Autodesk Fusion 360 part; units mm, degrees
(part 8 of 8)
equation "d2441 = ( ( ( keyRowTwo ) - holderStemY ) - 5.1 mm ) + faceOriginV"
equation "d2442 = ( ( ( ( layoutGap + keycapSize / 2 + 1 * keyPitch ) - holderStemX ) - holderFrameX / 2 - 0.1 mm ) + ( holderFrameX / 2 - holderWidth / 2 + 0.1 mm ) ) - ( ( ( layoutGap + keycapSize / 2 + 1 * keyPitch ) - holderStemX ) - holderFrameX / 2 - 0.1 mm )"
equation "d2443 = ( ( ( ( ( keyRowTwo ) - holderStemY ) - 5.1 mm ) + faceOriginV ) + ( 7.8 mm ) ) - ( ( ( ( keyRowTwo ) - holderStemY ) - 5.1 mm ) + faceOriginV )"
equation "d2444 = -( holderHeight + holderHookThickness - 1.2 mm + 0.2 mm )"
equation "d2446 = ( ( layoutGap + keycapSize / 2 + 1 * keyPitch ) - holderStemX ) + holderWidth / 2"
equation "d2447 = ( ( ( keyRowTwo ) - holderStemY ) - 5.1 mm ) + faceOriginV"
equation "d2448 = ( ( ( ( layoutGap + keycapSize / 2 + 1 * keyPitch ) - holderStemX ) + holderWidth / 2 ) + ( holderFrameX / 2 - holderWidth / 2 + 0.1 mm ) ) - ( ( ( layoutGap + keycapSize / 2 + 1 * keyPitch ) - holderStemX ) + holderWidth / 2 )"
equation "d2449 = ( ( ( ( ( keyRowTwo ) - holderStemY ) - 5.1 mm ) + faceOriginV ) + ( 7.8 mm ) ) - ( ( ( ( keyRowTwo ) - holderStemY ) - 5.1 mm ) + faceOriginV )"
equation "d2450 = -( holderHeight + holderHookThickness - 1.2 mm + 0.2 mm )"
equation "d2452 = ( ( layoutGap + keycapSize / 2 + 1 * keyPitch ) - holderStemX ) + ( -2.5 mm ) - 1.2 mm"
equation "d2453 = ( ( ( ( keyRowTwo ) - holderStemY ) - 1.2 mm ) * cos(caseTilt) + ( holderBottomDepth + holderLidGap ) * sin(caseTilt) ) - 2.5 mm"
equation "d2454 = ( ( ( ( layoutGap + keycapSize / 2 + 1 * keyPitch ) - holderStemX ) + ( -2.5 mm ) - 1.2 mm ) + ( 2.4 mm ) ) - ( ( ( layoutGap + keycapSize / 2 + 1 * keyPitch ) - holderStemX ) + ( -2.5 mm ) - 1.2 mm )"
equation "d2455 = ( ( ( ( ( ( keyRowTwo ) - holderStemY ) - 1.2 mm ) * cos(caseTilt) + ( holderBottomDepth + holderLidGap ) * sin(caseTilt) ) - 2.5 mm ) + ( 5 mm ) ) - ( ( ( ( ( keyRowTwo ) - holderStemY ) - 1.2 mm ) * cos(caseTilt) + ( holderBottomDepth + holderLidGap ) * sin(caseTilt) ) - 2.5 mm )"
equation "d2456 = ( frontHeight + ( ( ( keyRowTwo ) - holderStemY ) - 1.2 mm ) * sin(caseTilt) - ( holderBottomDepth + holderLidGap ) * cos(caseTilt) ) - bottomThickness - 2 mm"
equation "d2458 = ( ( layoutGap + keycapSize / 2 + 1 * keyPitch ) - holderStemX ) + ( -2.5 mm ) - 0.5 mm"
equation "d2459 = ( ( ( ( keyRowTwo ) - holderStemY ) - 1.2 mm ) * cos(caseTilt) + ( holderBottomDepth + holderLidGap ) * sin(caseTilt) ) - 1.5 mm"
equation "d2460 = ( ( ( ( layoutGap + keycapSize / 2 + 1 * keyPitch ) - holderStemX ) + ( -2.5 mm ) - 0.5 mm ) + ( 1 mm ) ) - ( ( ( layoutGap + keycapSize / 2 + 1 * keyPitch ) - holderStemX ) + ( -2.5 mm ) - 0.5 mm )"
equation "d2461 = ( ( ( ( ( ( keyRowTwo ) - holderStemY ) - 1.2 mm ) * cos(caseTilt) + ( holderBottomDepth + holderLidGap ) * sin(caseTilt) ) - 1.5 mm ) + ( 3 mm ) ) - ( ( ( ( ( keyRowTwo ) - holderStemY ) - 1.2 mm ) * cos(caseTilt) + ( holderBottomDepth + holderLidGap ) * sin(caseTilt) ) - 1.5 mm )"
equation "d2462 = ( frontHeight + ( ( ( keyRowTwo ) - holderStemY ) - 1.2 mm ) * sin(caseTilt) - ( holderBottomDepth + holderLidGap ) * cos(caseTilt) ) - bottomThickness + 0.5 mm"
equation "d2464 = ( ( ( layoutGap + keycapSize / 2 + 1 * keyPitch ) - holderStemX ) + ( -2.5 mm ) - 0.5 mm ) - 0.1 mm"
equation "d2465 = ( ( ( ( keyRowTwo ) - holderStemY ) - 1.2 mm ) - 2 mm ) + faceOriginV"
equation "d2466 = ( ( ( ( ( layoutGap + keycapSize / 2 + 1 * keyPitch ) - holderStemX ) + ( -2.5 mm ) - 0.5 mm ) - 0.1 mm ) + ( 1.2 mm ) ) - ( ( ( ( layoutGap + keycapSize / 2 + 1 * keyPitch ) - holderStemX ) + ( -2.5 mm ) - 0.5 mm ) - 0.1 mm )"
equation "d2467 = ( ( ( ( ( ( keyRowTwo ) - holderStemY ) - 1.2 mm ) - 2 mm ) + faceOriginV ) + ( 4 mm ) ) - ( ( ( ( ( keyRowTwo ) - holderStemY ) - 1.2 mm ) - 2 mm ) + faceOriginV )"
equation "d2468 = rearHeight"
equation "d2470 = ( ( layoutGap + keycapSize / 2 + 1 * keyPitch ) - holderStemX ) + ( 2.5 mm ) - 1.2 mm"
equation "d2471 = ( ( ( ( keyRowTwo ) - holderStemY ) - 1.2 mm ) * cos(caseTilt) + ( holderBottomDepth + holderLidGap ) * sin(caseTilt) ) - 2.5 mm"
equation "d2472 = ( ( ( ( layoutGap + keycapSize / 2 + 1 * keyPitch ) - holderStemX ) + ( 2.5 mm ) - 1.2 mm ) + ( 2.4 mm ) ) - ( ( ( layoutGap + keycapSize / 2 + 1 * keyPitch ) - holderStemX ) + ( 2.5 mm ) - 1.2 mm )"
equation "d2473 = ( ( ( ( ( ( keyRowTwo ) - holderStemY ) - 1.2 mm ) * cos(caseTilt) + ( holderBottomDepth + holderLidGap ) * sin(caseTilt) ) - 2.5 mm ) + ( 5 mm ) ) - ( ( ( ( ( keyRowTwo ) - holderStemY ) - 1.2 mm ) * cos(caseTilt) + ( holderBottomDepth + holderLidGap ) * sin(caseTilt) ) - 2.5 mm )"
equation "d2474 = ( frontHeight + ( ( ( keyRowTwo ) - holderStemY ) - 1.2 mm ) * sin(caseTilt) - ( holderBottomDepth + holderLidGap ) * cos(caseTilt) ) - bottomThickness - 2 mm"
equation "d2476 = ( ( layoutGap + keycapSize / 2 + 1 * keyPitch ) - holderStemX ) + ( 2.5 mm ) - 0.5 mm"
equation "d2477 = ( ( ( ( keyRowTwo ) - holderStemY ) - 1.2 mm ) * cos(caseTilt) + ( holderBottomDepth + holderLidGap ) * sin(caseTilt) ) - 1.5 mm"
equation "d2478 = ( ( ( ( layoutGap + keycapSize / 2 + 1 * keyPitch ) - holderStemX ) + ( 2.5 mm ) - 0.5 mm ) + ( 1 mm ) ) - ( ( ( layoutGap + keycapSize / 2 + 1 * keyPitch ) - holderStemX ) + ( 2.5 mm ) - 0.5 mm )"
equation "d2479 = ( ( ( ( ( ( keyRowTwo ) - holderStemY ) - 1.2 mm ) * cos(caseTilt) + ( holderBottomDepth + holderLidGap ) * sin(caseTilt) ) - 1.5 mm ) + ( 3 mm ) ) - ( ( ( ( ( keyRowTwo ) - holderStemY ) - 1.2 mm ) * cos(caseTilt) + ( holderBottomDepth + holderLidGap ) * sin(caseTilt) ) - 1.5 mm )"
equation "d2480 = ( frontHeight + ( ( ( keyRowTwo ) - holderStemY ) - 1.2 mm ) * sin(caseTilt) - ( holderBottomDepth + holderLidGap ) * cos(caseTilt) ) - bottomThickness + 0.5 mm"
equation "d2482 = ( ( ( layoutGap + keycapSize / 2 + 1 * keyPitch ) - holderStemX ) + ( 2.5 mm ) - 0.5 mm ) - 0.1 mm"
equation "d2483 = ( ( ( ( keyRowTwo ) - holderStemY ) - 1.2 mm ) - 2 mm ) + faceOriginV"
equation "d2484 = ( ( ( ( ( layoutGap + keycapSize / 2 + 1 * keyPitch ) - holderStemX ) + ( 2.5 mm ) - 0.5 mm ) - 0.1 mm ) + ( 1.2 mm ) ) - ( ( ( ( layoutGap + keycapSize / 2 + 1 * keyPitch ) - holderStemX ) + ( 2.5 mm ) - 0.5 mm ) - 0.1 mm )"
equation "d2485 = ( ( ( ( ( ( keyRowTwo ) - holderStemY ) - 1.2 mm ) - 2 mm ) + faceOriginV ) + ( 4 mm ) ) - ( ( ( ( ( keyRowTwo ) - holderStemY ) - 1.2 mm ) - 2 mm ) + faceOriginV )"
equation "d2486 = rearHeight"
equation "d2488 = ( layoutGap + keycapSize / 2 + 2 * keyPitch ) - holderFrameX / 2"
equation "d2489 = ( ( keyRowTwo ) - holderFrameY / 2 ) + faceOriginV"
equation "d2490 = ( ( ( layoutGap + keycapSize / 2 + 2 * keyPitch ) - holderFrameX / 2 ) + ( holderFrameX ) ) - ( ( layoutGap + keycapSize / 2 + 2 * keyPitch ) - holderFrameX / 2 )"
equation "d2491 = ( ( ( ( keyRowTwo ) - holderFrameY / 2 ) + faceOriginV ) + ( holderFrameY ) ) - ( ( ( keyRowTwo ) - holderFrameY / 2 ) + faceOriginV )"
equation "d2492 = -( holderBottomDepth + holderHookThickness - shellWall - carrierClearance - carrierThickness )"
equation "d2494 = ( layoutGap + keycapSize / 2 + 2 * keyPitch ) - holderSwitchVoid / 2"
equation "d2495 = ( ( keyRowTwo ) - holderSwitchVoid / 2 ) + faceOriginV"
equation "d2496 = ( ( ( layoutGap + keycapSize / 2 + 2 * keyPitch ) - holderSwitchVoid / 2 ) + ( holderSwitchVoid ) ) - ( ( layoutGap + keycapSize / 2 + 2 * keyPitch ) - holderSwitchVoid / 2 )"
equation "d2497 = ( ( ( ( keyRowTwo ) - holderSwitchVoid / 2 ) + faceOriginV ) + ( holderSwitchVoid ) ) - ( ( ( keyRowTwo ) - holderSwitchVoid / 2 ) + faceOriginV )"
equation "d2498 = -( holderTopDepth - shellWall - carrierClearance - carrierThickness )"
equation "d2500 = ( ( layoutGap + keycapSize / 2 + 2 * keyPitch ) - holderStemX ) - holderWidth / 2 - holderFit"
equation "d2501 = ( ( ( keyRowTwo ) - holderStemY ) - holderLength / 2 - holderFit ) + faceOriginV"
equation "d2502 = ( ( ( ( layoutGap + keycapSize / 2 + 2 * keyPitch ) - holderStemX ) - holderWidth / 2 - holderFit ) + ( holderWidth + 2 * holderFit ) ) - ( ( ( layoutGap + keycapSize / 2 + 2 * keyPitch ) - holderStemX ) - holderWidth / 2 - holderFit )"
equation "d2503 = ( ( ( ( ( keyRowTwo ) - holderStemY ) - holderLength / 2 - holderFit ) + faceOriginV ) + ( holderLength + 2 * holderFit ) ) - ( ( ( ( keyRowTwo ) - holderStemY ) - holderLength / 2 - holderFit ) + faceOriginV )"
equation "d2504 = -( holderHeight + holderHookThickness + 0.2 mm )"
equation "d2506 = ( ( layoutGap + keycapSize / 2 + 2 * keyPitch ) - holderStemX ) - holderFrameX / 2 - 0.1 mm"
equation "d2507 = ( ( ( ( keyRowTwo ) - holderStemY ) + holderSpringY ) - holderSpringWidth / 2 - 0.6 mm ) + faceOriginV"
equation "d2508 = ( ( ( ( layoutGap + keycapSize / 2 + 2 * keyPitch ) - holderStemX ) - holderFrameX / 2 - 0.1 mm ) + ( holderFrameX / 2 - holderWidth / 2 - holderFit + 0.1 mm ) ) - ( ( ( layoutGap + keycapSize / 2 + 2 * keyPitch ) - holderStemX ) - holderFrameX / 2 - 0.1 mm )"
equation "d2509 = ( ( ( ( ( ( keyRowTwo ) - holderStemY ) + holderSpringY ) - holderSpringWidth / 2 - 0.6 mm ) + faceOriginV ) + ( 0.6 mm ) ) - ( ( ( ( ( keyRowTwo ) - holderStemY ) + holderSpringY ) - holderSpringWidth / 2 - 0.6 mm ) + faceOriginV )"
equation "d2510 = -( holderBottomDepth + holderHookThickness - shellWall - carrierClearance - carrierThickness - 1 mm + 0.2 mm )"
equation "d2512 = ( ( layoutGap + keycapSize / 2 + 2 * keyPitch ) - holderStemX ) - holderFrameX / 2 - 0.1 mm"
equation "d2513 = ( ( ( ( keyRowTwo ) - holderStemY ) + holderSpringY ) + holderSpringWidth / 2 ) + faceOriginV"
equation "d2514 = ( ( ( ( layoutGap + keycapSize / 2 + 2 * keyPitch ) - holderStemX ) - holderFrameX / 2 - 0.1 mm ) + ( holderFrameX / 2 - holderWidth / 2 - holderFit + 0.1 mm ) ) - ( ( ( layoutGap + keycapSize / 2 + 2 * keyPitch ) - holderStemX ) - holderFrameX / 2 - 0.1 mm )"
equation "d2515 = ( ( ( ( ( ( keyRowTwo ) - holderStemY ) + holderSpringY ) + holderSpringWidth / 2 ) + faceOriginV ) + ( 0.6 mm ) ) - ( ( ( ( ( keyRowTwo ) - holderStemY ) + holderSpringY ) + holderSpringWidth / 2 ) + faceOriginV )"
equation "d2516 = -( holderBottomDepth + holderHookThickness - shellWall - carrierClearance - carrierThickness - 1 mm + 0.2 mm )"
equation "d2518 = ( ( layoutGap + keycapSize / 2 + 2 * keyPitch ) - holderStemX ) - holderFrameX / 2 + 0.8 mm"
equation "d2519 = ( ( ( ( keyRowTwo ) - holderStemY ) + holderSpringY ) - holderSpringWidth / 2 ) + faceOriginV"
equation "d2520 = ( ( ( ( layoutGap + keycapSize / 2 + 2 * keyPitch ) - holderStemX ) - holderFrameX / 2 + 0.8 mm ) + ( holderFrameX / 2 - 0.8 mm - holderWidth / 2 - holderFit ) ) - ( ( ( layoutGap + keycapSize / 2 + 2 * keyPitch ) - holderStemX ) - holderFrameX / 2 + 0.8 mm )"
equation "d2521 = ( ( ( ( ( ( keyRowTwo ) - holderStemY ) + holderSpringY ) - holderSpringWidth / 2 ) + faceOriginV ) + ( holderSpringWidth ) ) - ( ( ( ( ( keyRowTwo ) - holderStemY ) + holderSpringY ) - holderSpringWidth / 2 ) + faceOriginV )"
equation "d2522 = -( holderHeight + holderHookThickness + 0.2 mm )"
equation "d2524 = ( ( layoutGap + keycapSize / 2 + 2 * keyPitch ) - holderStemX ) - holderFrameX / 2"
equation "d2525 = ( ( ( ( keyRowTwo ) - holderStemY ) + holderSpringY ) - holderSpringWidth / 2 ) + faceOriginV"
equation "d2526 = ( ( ( ( layoutGap + keycapSize / 2 + 2 * keyPitch ) - holderStemX ) - holderFrameX / 2 ) + ( holderFrameX / 2 - holderWidth / 2 + holderHookOverlap ) ) - ( ( ( layoutGap + keycapSize / 2 + 2 * keyPitch ) - holderStemX ) - holderFrameX / 2 )"
equation "d2527 = ( ( ( ( ( ( keyRowTwo ) - holderStemY ) + holderSpringY ) - holderSpringWidth / 2 ) + faceOriginV ) + ( holderSpringWidth ) ) - ( ( ( ( ( keyRowTwo ) - holderStemY ) + holderSpringY ) - holderSpringWidth / 2 ) + faceOriginV )"
equation "d2528 = -( holderHookThickness )"
equation "d2531 = ( ( layoutGap + keycapSize / 2 + 2 * keyPitch ) - holderStemX ) + holderWidth / 2 + holderFit"
equation "d2532 = ( ( ( ( keyRowTwo ) - holderStemY ) + holderSpringY ) - holderSpringWidth / 2 - 0.6 mm ) + faceOriginV"
equation "d2533 = ( ( ( ( layoutGap + keycapSize / 2 + 2 * keyPitch ) - holderStemX ) + holderWidth / 2 + holderFit ) + ( holderFrameX / 2 - holderWidth / 2 - holderFit + 0.1 mm ) ) - ( ( ( layoutGap + keycapSize / 2 + 2 * keyPitch ) - holderStemX ) + holderWidth / 2 + holderFit )"
equation "d2534 = ( ( ( ( ( ( keyRowTwo ) - holderStemY ) + holderSpringY ) - holderSpringWidth / 2 - 0.6 mm ) + faceOriginV ) + ( 0.6 mm ) ) - ( ( ( ( ( keyRowTwo ) - holderStemY ) + holderSpringY ) - holderSpringWidth / 2 - 0.6 mm ) + faceOriginV )"
equation "d2535 = -( holderBottomDepth + holderHookThickness - shellWall - carrierClearance - carrierThickness - 1 mm + 0.2 mm )"
equation "d2537 = ( ( layoutGap + keycapSize / 2 + 2 * keyPitch ) - holderStemX ) + holderWidth / 2 + holderFit"
equation "d2538 = ( ( ( ( keyRowTwo ) - holderStemY ) + holderSpringY ) + holderSpringWidth / 2 ) + faceOriginV"
equation "d2539 = ( ( ( ( layoutGap + keycapSize / 2 + 2 * keyPitch ) - holderStemX ) + holderWidth / 2 + holderFit ) + ( holderFrameX / 2 - holderWidth / 2 - holderFit + 0.1 mm ) ) - ( ( ( layoutGap + keycapSize / 2 + 2 * keyPitch ) - holderStemX ) + holderWidth / 2 + holderFit )"
equation "d2540 = ( ( ( ( ( ( keyRowTwo ) - holderStemY ) + holderSpringY ) + holderSpringWidth / 2 ) + faceOriginV ) + ( 0.6 mm ) ) - ( ( ( ( ( keyRowTwo ) - holderStemY ) + holderSpringY ) + holderSpringWidth / 2 ) + faceOriginV )"
equation "d2541 = -( holderBottomDepth + holderHookThickness - shellWall - carrierClearance - carrierThickness - 1 mm + 0.2 mm )"
equation "d2543 = ( ( layoutGap + keycapSize / 2 + 2 * keyPitch ) - holderStemX ) + holderWidth / 2 + holderFit"
equation "d2544 = ( ( ( ( keyRowTwo ) - holderStemY ) + holderSpringY ) - holderSpringWidth / 2 ) + faceOriginV"
equation "d2545 = ( ( ( ( layoutGap + keycapSize / 2 + 2 * keyPitch ) - holderStemX ) + holderWidth / 2 + holderFit ) + ( holderFrameX / 2 - 0.8 mm - holderWidth / 2 - holderFit ) ) - ( ( ( layoutGap + keycapSize / 2 + 2 * keyPitch ) - holderStemX ) + holderWidth / 2 + holderFit )"
equation "d2546 = ( ( ( ( ( ( keyRowTwo ) - holderStemY ) + holderSpringY ) - holderSpringWidth / 2 ) + faceOriginV ) + ( holderSpringWidth ) ) - ( ( ( ( ( keyRowTwo ) - holderStemY ) + holderSpringY ) - holderSpringWidth / 2 ) + faceOriginV )"
equation "d2547 = -( holderHeight + holderHookThickness + 0.2 mm )"
equation "d2549 = ( ( layoutGap + keycapSize / 2 + 2 * keyPitch ) - holderStemX ) + holderWidth / 2 - holderHookOverlap"
equation "d2550 = ( ( ( ( keyRowTwo ) - holderStemY ) + holderSpringY ) - holderSpringWidth / 2 ) + faceOriginV"
equation "d2551 = ( ( ( ( layoutGap + keycapSize / 2 + 2 * keyPitch ) - holderStemX ) + holderWidth / 2 - holderHookOverlap ) + ( holderFrameX / 2 - holderWidth / 2 + holderHookOverlap ) ) - ( ( ( layoutGap + keycapSize / 2 + 2 * keyPitch ) - holderStemX ) + holderWidth / 2 - holderHookOverlap )"
equation "d2552 = ( ( ( ( ( ( keyRowTwo ) - holderStemY ) + holderSpringY ) - holderSpringWidth / 2 ) + faceOriginV ) + ( holderSpringWidth ) ) - ( ( ( ( ( keyRowTwo ) - holderStemY ) + holderSpringY ) - holderSpringWidth / 2 ) + faceOriginV )"
equation "d2553 = -( holderHookThickness )"
equation "d2556 = ( ( layoutGap + keycapSize / 2 + 2 * keyPitch ) - holderStemX ) + ( -3 mm ) - 0.5 mm"
equation "d2557 = ( ( ( keyRowTwo ) - holderStemY ) + 4 mm ) + faceOriginV"
equation "d2558 = ( ( ( ( layoutGap + keycapSize / 2 + 2 * keyPitch ) - holderStemX ) + ( -3 mm ) - 0.5 mm ) + ( 1 mm ) ) - ( ( ( layoutGap + keycapSize / 2 + 2 * keyPitch ) - holderStemX ) + ( -3 mm ) - 0.5 mm )"
equation "d2559 = ( ( ( ( ( keyRowTwo ) - holderStemY ) + 4 mm ) + faceOriginV ) + ( holderFrameY / 2 - 4 mm ) ) - ( ( ( ( keyRowTwo ) - holderStemY ) + 4 mm ) + faceOriginV )"
equation "d2562 = ( ( layoutGap + keycapSize / 2 + 2 * keyPitch ) - holderStemX ) + ( 3 mm ) - 0.5 mm"
equation "d2563 = ( ( ( keyRowTwo ) - holderStemY ) + 4 mm ) + faceOriginV"
equation "d2564 = ( ( ( ( layoutGap + keycapSize / 2 + 2 * keyPitch ) - holderStemX ) + ( 3 mm ) - 0.5 mm ) + ( 1 mm ) ) - ( ( ( layoutGap + keycapSize / 2 + 2 * keyPitch ) - holderStemX ) + ( 3 mm ) - 0.5 mm )"
equation "d2565 = ( ( ( ( ( keyRowTwo ) - holderStemY ) + 4 mm ) + faceOriginV ) + ( holderFrameY / 2 - 4 mm ) ) - ( ( ( ( keyRowTwo ) - holderStemY ) + 4 mm ) + faceOriginV )"
equation "d2568 = ( ( layoutGap + keycapSize / 2 + 2 * keyPitch ) - holderStemX ) - holderFrameX / 2 - 0.1 mm"
equation "d2569 = ( ( ( keyRowTwo ) - holderStemY ) - 5.1 mm ) + faceOriginV"
equation "d2570 = ( ( ( ( layoutGap + keycapSize / 2 + 2 * keyPitch ) - holderStemX ) - holderFrameX / 2 - 0.1 mm ) + ( holderFrameX / 2 - holderWidth / 2 + 0.1 mm ) ) - ( ( ( layoutGap + keycapSize / 2 + 2 * keyPitch ) - holderStemX ) - holderFrameX / 2 - 0.1 mm )"
equation "d2571 = ( ( ( ( ( keyRowTwo ) - holderStemY ) - 5.1 mm ) + faceOriginV ) + ( 7.8 mm ) ) - ( ( ( ( keyRowTwo ) - holderStemY ) - 5.1 mm ) + faceOriginV )"
equation "d2572 = -( holderHeight + holderHookThickness - 1.2 mm + 0.2 mm )"
equation "d2574 = ( ( layoutGap + keycapSize / 2 + 2 * keyPitch ) - holderStemX ) + holderWidth / 2"
equation "d2575 = ( ( ( keyRowTwo ) - holderStemY ) - 5.1 mm ) + faceOriginV"
equation "d2576 = ( ( ( ( layoutGap + keycapSize / 2 + 2 * keyPitch ) - holderStemX ) + holderWidth / 2 ) + ( holderFrameX / 2 - holderWidth / 2 + 0.1 mm ) ) - ( ( ( layoutGap + keycapSize / 2 + 2 * keyPitch ) - holderStemX ) + holderWidth / 2 )"
equation "d2577 = ( ( ( ( ( keyRowTwo ) - holderStemY ) - 5.1 mm ) + faceOriginV ) + ( 7.8 mm ) ) - ( ( ( ( keyRowTwo ) - holderStemY ) - 5.1 mm ) + faceOriginV )"
equation "d2578 = -( holderHeight + holderHookThickness - 1.2 mm + 0.2 mm )"
equation "d2580 = ( ( layoutGap + keycapSize / 2 + 2 * keyPitch ) - holderStemX ) + ( -2.5 mm ) - 1.2 mm"
equation "d2581 = ( ( ( ( keyRowTwo ) - holderStemY ) - 1.2 mm ) * cos(caseTilt) + ( holderBottomDepth + holderLidGap ) * sin(caseTilt) ) - 2.5 mm"
equation "d2582 = ( ( ( ( layoutGap + keycapSize / 2 + 2 * keyPitch ) - holderStemX ) + ( -2.5 mm ) - 1.2 mm ) + ( 2.4 mm ) ) - ( ( ( layoutGap + keycapSize / 2 + 2 * keyPitch ) - holderStemX ) + ( -2.5 mm ) - 1.2 mm )"
equation "d2583 = ( ( ( ( ( ( keyRowTwo ) - holderStemY ) - 1.2 mm ) * cos(caseTilt) + ( holderBottomDepth + holderLidGap ) * sin(caseTilt) ) - 2.5 mm ) + ( 5 mm ) ) - ( ( ( ( ( keyRowTwo ) - holderStemY ) - 1.2 mm ) * cos(caseTilt) + ( holderBottomDepth + holderLidGap ) * sin(caseTilt) ) - 2.5 mm )"
equation "d2584 = ( frontHeight + ( ( ( keyRowTwo ) - holderStemY ) - 1.2 mm ) * sin(caseTilt) - ( holderBottomDepth + holderLidGap ) * cos(caseTilt) ) - bottomThickness - 2 mm"
equation "d2586 = ( ( layoutGap + keycapSize / 2 + 2 * keyPitch ) - holderStemX ) + ( -2.5 mm ) - 0.5 mm"
equation "d2587 = ( ( ( ( keyRowTwo ) - holderStemY ) - 1.2 mm ) * cos(caseTilt) + ( holderBottomDepth + holderLidGap ) * sin(caseTilt) ) - 1.5 mm"
equation "d2588 = ( ( ( ( layoutGap + keycapSize / 2 + 2 * keyPitch ) - holderStemX ) + ( -2.5 mm ) - 0.5 mm ) + ( 1 mm ) ) - ( ( ( layoutGap + keycapSize / 2 + 2 * keyPitch ) - holderStemX ) + ( -2.5 mm ) - 0.5 mm )"
equation "d2589 = ( ( ( ( ( ( keyRowTwo ) - holderStemY ) - 1.2 mm ) * cos(caseTilt) + ( holderBottomDepth + holderLidGap ) * sin(caseTilt) ) - 1.5 mm ) + ( 3 mm ) ) - ( ( ( ( ( keyRowTwo ) - holderStemY ) - 1.2 mm ) * cos(caseTilt) + ( holderBottomDepth + holderLidGap ) * sin(caseTilt) ) - 1.5 mm )"
equation "d2590 = ( frontHeight + ( ( ( keyRowTwo ) - holderStemY ) - 1.2 mm ) * sin(caseTilt) - ( holderBottomDepth + holderLidGap ) * cos(caseTilt) ) - bottomThickness + 0.5 mm"
equation "d2592 = ( ( ( layoutGap + keycapSize / 2 + 2 * keyPitch ) - holderStemX ) + ( -2.5 mm ) - 0.5 mm ) - 0.1 mm"
equation "d2593 = ( ( ( ( keyRowTwo ) - holderStemY ) - 1.2 mm ) - 2 mm ) + faceOriginV"
equation "d2594 = ( ( ( ( ( layoutGap + keycapSize / 2 + 2 * keyPitch ) - holderStemX ) + ( -2.5 mm ) - 0.5 mm ) - 0.1 mm ) + ( 1.2 mm ) ) - ( ( ( ( layoutGap + keycapSize / 2 + 2 * keyPitch ) - holderStemX ) + ( -2.5 mm ) - 0.5 mm ) - 0.1 mm )"
equation "d2595 = ( ( ( ( ( ( keyRowTwo ) - holderStemY ) - 1.2 mm ) - 2 mm ) + faceOriginV ) + ( 4 mm ) ) - ( ( ( ( ( keyRowTwo ) - holderStemY ) - 1.2 mm ) - 2 mm ) + faceOriginV )"
equation "d2596 = rearHeight"
equation "d2598 = ( ( layoutGap + keycapSize / 2 + 2 * keyPitch ) - holderStemX ) + ( 2.5 mm ) - 1.2 mm"
equation "d2599 = ( ( ( ( keyRowTwo ) - holderStemY ) - 1.2 mm ) * cos(caseTilt) + ( holderBottomDepth + holderLidGap ) * sin(caseTilt) ) - 2.5 mm"
equation "d2600 = ( ( ( ( layoutGap + keycapSize / 2 + 2 * keyPitch ) - holderStemX ) + ( 2.5 mm ) - 1.2 mm ) + ( 2.4 mm ) ) - ( ( ( layoutGap + keycapSize / 2 + 2 * keyPitch ) - holderStemX ) + ( 2.5 mm ) - 1.2 mm )"
equation "d2601 = ( ( ( ( ( ( keyRowTwo ) - holderStemY ) - 1.2 mm ) * cos(caseTilt) + ( holderBottomDepth + holderLidGap ) * sin(caseTilt) ) - 2.5 mm ) + ( 5 mm ) ) - ( ( ( ( ( keyRowTwo ) - holderStemY ) - 1.2 mm ) * cos(caseTilt) + ( holderBottomDepth + holderLidGap ) * sin(caseTilt) ) - 2.5 mm )"
equation "d2602 = ( frontHeight + ( ( ( keyRowTwo ) - holderStemY ) - 1.2 mm ) * sin(caseTilt) - ( holderBottomDepth + holderLidGap ) * cos(caseTilt) ) - bottomThickness - 2 mm"
equation "d2604 = ( ( layoutGap + keycapSize / 2 + 2 * keyPitch ) - holderStemX ) + ( 2.5 mm ) - 0.5 mm"
equation "d2605 = ( ( ( ( keyRowTwo ) - holderStemY ) - 1.2 mm ) * cos(caseTilt) + ( holderBottomDepth + holderLidGap ) * sin(caseTilt) ) - 1.5 mm"
equation "d2606 = ( ( ( ( layoutGap + keycapSize / 2 + 2 * keyPitch ) - holderStemX ) + ( 2.5 mm ) - 0.5 mm ) + ( 1 mm ) ) - ( ( ( layoutGap + keycapSize / 2 + 2 * keyPitch ) - holderStemX ) + ( 2.5 mm ) - 0.5 mm )"
equation "d2607 = ( ( ( ( ( ( keyRowTwo ) - holderStemY ) - 1.2 mm ) * cos(caseTilt) + ( holderBottomDepth + holderLidGap ) * sin(caseTilt) ) - 1.5 mm ) + ( 3 mm ) ) - ( ( ( ( ( keyRowTwo ) - holderStemY ) - 1.2 mm ) * cos(caseTilt) + ( holderBottomDepth + holderLidGap ) * sin(caseTilt) ) - 1.5 mm )"
equation "d2608 = ( frontHeight + ( ( ( keyRowTwo ) - holderStemY ) - 1.2 mm ) * sin(caseTilt) - ( holderBottomDepth + holderLidGap ) * cos(caseTilt) ) - bottomThickness + 0.5 mm"
equation "d2610 = ( ( ( layoutGap + keycapSize / 2 + 2 * keyPitch ) - holderStemX ) + ( 2.5 mm ) - 0.5 mm ) - 0.1 mm"
equation "d2611 = ( ( ( ( keyRowTwo ) - holderStemY ) - 1.2 mm ) - 2 mm ) + faceOriginV"
equation "d2612 = ( ( ( ( ( layoutGap + keycapSize / 2 + 2 * keyPitch ) - holderStemX ) + ( 2.5 mm ) - 0.5 mm ) - 0.1 mm ) + ( 1.2 mm ) ) - ( ( ( ( layoutGap + keycapSize / 2 + 2 * keyPitch ) - holderStemX ) + ( 2.5 mm ) - 0.5 mm ) - 0.1 mm )"
equation "d2613 = ( ( ( ( ( ( keyRowTwo ) - holderStemY ) - 1.2 mm ) - 2 mm ) + faceOriginV ) + ( 4 mm ) ) - ( ( ( ( ( keyRowTwo ) - holderStemY ) - 1.2 mm ) - 2 mm ) + faceOriginV )"
equation "d2614 = rearHeight"
equation "d2616 = layoutGap + ( displayWidth - oledBoardWidth ) / 2 - oledFitClearance"
equation "d2617 = ( controlCenter - oledBoardLength / 2 - oledFitClearance ) + faceOriginV"
equation "d2618 = ( ( layoutGap + ( displayWidth - oledBoardWidth ) / 2 - oledFitClearance ) + ( oledBoardWidth + 2 * oledFitClearance ) ) - ( layoutGap + ( displayWidth - oledBoardWidth ) / 2 - oledFitClearance )"
equation "d2619 = ( ( ( controlCenter - oledBoardLength / 2 - oledFitClearance ) + faceOriginV ) + ( oledBoardLength + 2 * oledFitClearance ) ) - ( ( controlCenter - oledBoardLength / 2 - oledFitClearance ) + faceOriginV )"
equation "d2620 = -( oledBackDepth + oledFitClearance - shellWall - carrierClearance )"
equation "d2622 = ( 115 mm ) - 11 mm"
equation "d2623 = ( ( keyRowOne ) - 11 mm ) + faceOriginV"
equation "d2624 = ( ( ( 115 mm ) - 11 mm ) + ( 22 mm ) ) - ( ( 115 mm ) - 11 mm )"
equation "d2625 = ( ( ( ( keyRowOne ) - 11 mm ) + faceOriginV ) + ( 22 mm ) ) - ( ( ( keyRowOne ) - 11 mm ) + faceOriginV )"
equation "d2626 = -( carrierThickness )"
equation "d2628 = ( 115 mm ) - switchOpening / 2"
equation "d2629 = ( ( keyRowOne ) - switchOpening / 2 ) + faceOriginV"
equation "d2630 = ( ( ( 115 mm ) - switchOpening / 2 ) + ( switchOpening ) ) - ( ( 115 mm ) - switchOpening / 2 )"
equation "d2631 = ( ( ( ( keyRowOne ) - switchOpening / 2 ) + faceOriginV ) + ( switchOpening ) ) - ( ( ( keyRowOne ) - switchOpening / 2 ) + faceOriginV )"
equation "d2632 = -( carrierThickness + 0.1 mm )"
equation "d2634 = ( 115 mm ) - holderFrameX / 2"
equation "d2635 = ( ( keyRowOne ) - holderFrameY / 2 ) + faceOriginV"
equation "d2636 = ( ( ( 115 mm ) - holderFrameX / 2 ) + ( holderFrameX ) ) - ( ( 115 mm ) - holderFrameX / 2 )"
equation "d2637 = ( ( ( ( keyRowOne ) - holderFrameY / 2 ) + faceOriginV ) + ( holderFrameY ) ) - ( ( ( keyRowOne ) - holderFrameY / 2 ) + faceOriginV )"
equation "d2638 = -( holderBottomDepth + holderHookThickness - shellWall - carrierClearance - carrierThickness )"
equation "d2640 = ( 115 mm ) - holderSwitchVoid / 2"
equation "d2641 = ( ( keyRowOne ) - holderSwitchVoid / 2 ) + faceOriginV"
equation "d2642 = ( ( ( 115 mm ) - holderSwitchVoid / 2 ) + ( holderSwitchVoid ) ) - ( ( 115 mm ) - holderSwitchVoid / 2 )"
equation "d2643 = ( ( ( ( keyRowOne ) - holderSwitchVoid / 2 ) + faceOriginV ) + ( holderSwitchVoid ) ) - ( ( ( keyRowOne ) - holderSwitchVoid / 2 ) + faceOriginV )"
equation "d2644 = -( holderTopDepth - shellWall - carrierClearance - carrierThickness )"
equation "d2646 = ( ( 115 mm ) - holderStemX ) - holderWidth / 2 - holderFit"
equation "d2647 = ( ( ( keyRowOne ) - holderStemY ) - holderLength / 2 - holderFit ) + faceOriginV"
equation "d2648 = ( ( ( ( 115 mm ) - holderStemX ) - holderWidth / 2 - holderFit ) + ( holderWidth + 2 * holderFit ) ) - ( ( ( 115 mm ) - holderStemX ) - holderWidth / 2 - holderFit )"
equation "d2649 = ( ( ( ( ( keyRowOne ) - holderStemY ) - holderLength / 2 - holderFit ) + faceOriginV ) + ( holderLength + 2 * holderFit ) ) - ( ( ( ( keyRowOne ) - holderStemY ) - holderLength / 2 - holderFit ) + faceOriginV )"
equation "d2650 = -( holderHeight + holderHookThickness + 0.2 mm )"
equation "d2652 = ( ( 115 mm ) - holderStemX ) - holderFrameX / 2 - 0.1 mm"
equation "d2653 = ( ( ( ( keyRowOne ) - holderStemY ) + holderSpringY ) - holderSpringWidth / 2 - 0.6 mm ) + faceOriginV"
equation "d2654 = ( ( ( ( 115 mm ) - holderStemX ) - holderFrameX / 2 - 0.1 mm ) + ( holderFrameX / 2 - holderWidth / 2 - holderFit + 0.1 mm ) ) - ( ( ( 115 mm ) - holderStemX ) - holderFrameX / 2 - 0.1 mm )"
equation "d2655 = ( ( ( ( ( ( keyRowOne ) - holderStemY ) + holderSpringY ) - holderSpringWidth / 2 - 0.6 mm ) + faceOriginV ) + ( 0.6 mm ) ) - ( ( ( ( ( keyRowOne ) - holderStemY ) + holderSpringY ) - holderSpringWidth / 2 - 0.6 mm ) + faceOriginV )"
equation "d2656 = -( holderBottomDepth + holderHookThickness - shellWall - carrierClearance - carrierThickness - 1 mm + 0.2 mm )"
equation "d2658 = ( ( 115 mm ) - holderStemX ) - holderFrameX / 2 - 0.1 mm"
equation "d2659 = ( ( ( ( keyRowOne ) - holderStemY ) + holderSpringY ) + holderSpringWidth / 2 ) + faceOriginV"
equation "d2660 = ( ( ( ( 115 mm ) - holderStemX ) - holderFrameX / 2 - 0.1 mm ) + ( holderFrameX / 2 - holderWidth / 2 - holderFit + 0.1 mm ) ) - ( ( ( 115 mm ) - holderStemX ) - holderFrameX / 2 - 0.1 mm )"
equation "d2661 = ( ( ( ( ( ( keyRowOne ) - holderStemY ) + holderSpringY ) + holderSpringWidth / 2 ) + faceOriginV ) + ( 0.6 mm ) ) - ( ( ( ( ( keyRowOne ) - holderStemY ) + holderSpringY ) + holderSpringWidth / 2 ) + faceOriginV )"
equation "d2662 = -( holderBottomDepth + holderHookThickness - shellWall - carrierClearance - carrierThickness - 1 mm + 0.2 mm )"
equation "d2664 = ( ( 115 mm ) - holderStemX ) - holderFrameX / 2 + 0.8 mm"
equation "d2665 = ( ( ( ( keyRowOne ) - holderStemY ) + holderSpringY ) - holderSpringWidth / 2 ) + faceOriginV"
equation "d2666 = ( ( ( ( 115 mm ) - holderStemX ) - holderFrameX / 2 + 0.8 mm ) + ( holderFrameX / 2 - 0.8 mm - holderWidth / 2 - holderFit ) ) - ( ( ( 115 mm ) - holderStemX ) - holderFrameX / 2 + 0.8 mm )"
equation "d2667 = ( ( ( ( ( ( keyRowOne ) - holderStemY ) + holderSpringY ) - holderSpringWidth / 2 ) + faceOriginV ) + ( holderSpringWidth ) ) - ( ( ( ( ( keyRowOne ) - holderStemY ) + holderSpringY ) - holderSpringWidth / 2 ) + faceOriginV )"
equation "d2668 = -( holderHeight + holderHookThickness + 0.2 mm )"
equation "d2670 = ( ( 115 mm ) - holderStemX ) - holderFrameX / 2"
equation "d2671 = ( ( ( ( keyRowOne ) - holderStemY ) + holderSpringY ) - holderSpringWidth / 2 ) + faceOriginV"
equation "d2672 = ( ( ( ( 115 mm ) - holderStemX ) - holderFrameX / 2 ) + ( holderFrameX / 2 - holderWidth / 2 + holderHookOverlap ) ) - ( ( ( 115 mm ) - holderStemX ) - holderFrameX / 2 )"
equation "d2673 = ( ( ( ( ( ( keyRowOne ) - holderStemY ) + holderSpringY ) - holderSpringWidth / 2 ) + faceOriginV ) + ( holderSpringWidth ) ) - ( ( ( ( ( keyRowOne ) - holderStemY ) + holderSpringY ) - holderSpringWidth / 2 ) + faceOriginV )"
equation "d2674 = -( holderHookThickness )"
equation "d2677 = ( ( 115 mm ) - holderStemX ) + holderWidth / 2 + holderFit"
equation "d2678 = ( ( ( ( keyRowOne ) - holderStemY ) + holderSpringY ) - holderSpringWidth / 2 - 0.6 mm ) + faceOriginV"
equation "d2679 = ( ( ( ( 115 mm ) - holderStemX ) + holderWidth / 2 + holderFit ) + ( holderFrameX / 2 - holderWidth / 2 - holderFit + 0.1 mm ) ) - ( ( ( 115 mm ) - holderStemX ) + holderWidth / 2 + holderFit )"
equation "d2680 = ( ( ( ( ( ( keyRowOne ) - holderStemY ) + holderSpringY ) - holderSpringWidth / 2 - 0.6 mm ) + faceOriginV ) + ( 0.6 mm ) ) - ( ( ( ( ( keyRowOne ) - holderStemY ) + holderSpringY ) - holderSpringWidth / 2 - 0.6 mm ) + faceOriginV )"
equation "d2681 = -( holderBottomDepth + holderHookThickness - shellWall - carrierClearance - carrierThickness - 1 mm + 0.2 mm )"
equation "d2683 = ( ( 115 mm ) - holderStemX ) + holderWidth / 2 + holderFit"
equation "d2684 = ( ( ( ( keyRowOne ) - holderStemY ) + holderSpringY ) + holderSpringWidth / 2 ) + faceOriginV"
equation "d2685 = ( ( ( ( 115 mm ) - holderStemX ) + holderWidth / 2 + holderFit ) + ( holderFrameX / 2 - holderWidth / 2 - holderFit + 0.1 mm ) ) - ( ( ( 115 mm ) - holderStemX ) + holderWidth / 2 + holderFit )"
equation "d2686 = ( ( ( ( ( ( keyRowOne ) - holderStemY ) + holderSpringY ) + holderSpringWidth / 2 ) + faceOriginV ) + ( 0.6 mm ) ) - ( ( ( ( ( keyRowOne ) - holderStemY ) + holderSpringY ) + holderSpringWidth / 2 ) + faceOriginV )"
equation "d2687 = -( holderBottomDepth + holderHookThickness - shellWall - carrierClearance - carrierThickness - 1 mm + 0.2 mm )"
equation "d2689 = ( ( 115 mm ) - holderStemX ) + holderWidth / 2 + holderFit"
equation "d2690 = ( ( ( ( keyRowOne ) - holderStemY ) + holderSpringY ) - holderSpringWidth / 2 ) + faceOriginV"
equation "d2691 = ( ( ( ( 115 mm ) - holderStemX ) + holderWidth / 2 + holderFit ) + ( holderFrameX / 2 - 0.8 mm - holderWidth / 2 - holderFit ) ) - ( ( ( 115 mm ) - holderStemX ) + holderWidth / 2 + holderFit )"
equation "d2692 = ( ( ( ( ( ( keyRowOne ) - holderStemY ) + holderSpringY ) - holderSpringWidth / 2 ) + faceOriginV ) + ( holderSpringWidth ) ) - ( ( ( ( ( keyRowOne ) - holderStemY ) + holderSpringY ) - holderSpringWidth / 2 ) + faceOriginV )"
equation "d2693 = -( holderHeight + holderHookThickness + 0.2 mm )"
equation "d2695 = ( ( 115 mm ) - holderStemX ) + holderWidth / 2 - holderHookOverlap"
equation "d2696 = ( ( ( ( keyRowOne ) - holderStemY ) + holderSpringY ) - holderSpringWidth / 2 ) + faceOriginV"
equation "d2697 = ( ( ( ( 115 mm ) - holderStemX ) + holderWidth / 2 - holderHookOverlap ) + ( holderFrameX / 2 - holderWidth / 2 + holderHookOverlap ) ) - ( ( ( 115 mm ) - holderStemX ) + holderWidth / 2 - holderHookOverlap )"
equation "d2698 = ( ( ( ( ( ( keyRowOne ) - holderStemY ) + holderSpringY ) - holderSpringWidth / 2 ) + faceOriginV ) + ( holderSpringWidth ) ) - ( ( ( ( ( keyRowOne ) - holderStemY ) + holderSpringY ) - holderSpringWidth / 2 ) + faceOriginV )"
equation "d2699 = -( holderHookThickness )"
equation "d2702 = ( ( 115 mm ) - holderStemX ) + ( -3 mm ) - 0.5 mm"
equation "d2703 = ( ( ( keyRowOne ) - holderStemY ) + 4 mm ) + faceOriginV"
equation "d2704 = ( ( ( ( 115 mm ) - holderStemX ) + ( -3 mm ) - 0.5 mm ) + ( 1 mm ) ) - ( ( ( 115 mm ) - holderStemX ) + ( -3 mm ) - 0.5 mm )"
equation "d2705 = ( ( ( ( ( keyRowOne ) - holderStemY ) + 4 mm ) + faceOriginV ) + ( holderFrameY / 2 - 4 mm ) ) - ( ( ( ( keyRowOne ) - holderStemY ) + 4 mm ) + faceOriginV )"
equation "d2708 = ( ( 115 mm ) - holderStemX ) + ( 3 mm ) - 0.5 mm"
equation "d2709 = ( ( ( keyRowOne ) - holderStemY ) + 4 mm ) + faceOriginV"
equation "d2710 = ( ( ( ( 115 mm ) - holderStemX ) + ( 3 mm ) - 0.5 mm ) + ( 1 mm ) ) - ( ( ( 115 mm ) - holderStemX ) + ( 3 mm ) - 0.5 mm )"
equation "d2711 = ( ( ( ( ( keyRowOne ) - holderStemY ) + 4 mm ) + faceOriginV ) + ( holderFrameY / 2 - 4 mm ) ) - ( ( ( ( keyRowOne ) - holderStemY ) + 4 mm ) + faceOriginV )"
equation "d2714 = ( ( 115 mm ) - holderStemX ) - holderFrameX / 2 - 0.1 mm"
equation "d2715 = ( ( ( keyRowOne ) - holderStemY ) - 5.1 mm ) + faceOriginV"
equation "d2716 = ( ( ( ( 115 mm ) - holderStemX ) - holderFrameX / 2 - 0.1 mm ) + ( holderFrameX / 2 - holderWidth / 2 + 0.1 mm ) ) - ( ( ( 115 mm ) - holderStemX ) - holderFrameX / 2 - 0.1 mm )"
equation "d2717 = ( ( ( ( ( keyRowOne ) - holderStemY ) - 5.1 mm ) + faceOriginV ) + ( 7.8 mm ) ) - ( ( ( ( keyRowOne ) - holderStemY ) - 5.1 mm ) + faceOriginV )"
equation "d2718 = -( holderHeight + holderHookThickness - 1.2 mm + 0.2 mm )"
equation "d2720 = ( ( 115 mm ) - holderStemX ) + holderWidth / 2"
equation "d2721 = ( ( ( keyRowOne ) - holderStemY ) - 5.1 mm ) + faceOriginV"
equation "d2722 = ( ( ( ( 115 mm ) - holderStemX ) + holderWidth / 2 ) + ( holderFrameX / 2 - holderWidth / 2 + 0.1 mm ) ) - ( ( ( 115 mm ) - holderStemX ) + holderWidth / 2 )"
equation "d2723 = ( ( ( ( ( keyRowOne ) - holderStemY ) - 5.1 mm ) + faceOriginV ) + ( 7.8 mm ) ) - ( ( ( ( keyRowOne ) - holderStemY ) - 5.1 mm ) + faceOriginV )"
equation "d2724 = -( holderHeight + holderHookThickness - 1.2 mm + 0.2 mm )"
equation "d2726 = ( 115 mm ) - 11 mm"
equation "d2727 = ( ( keyRowOne ) * cos(caseTilt) + ( holderBottomDepth + holderLidGap ) * sin(caseTilt) ) - 11 mm"
equation "d2728 = ( ( ( 115 mm ) - 11 mm ) + ( 22 mm ) ) - ( ( 115 mm ) - 11 mm )"
equation "d2729 = ( ( ( ( keyRowOne ) * cos(caseTilt) + ( holderBottomDepth + holderLidGap ) * sin(caseTilt) ) - 11 mm ) + ( 22 mm ) ) - ( ( ( keyRowOne ) * cos(caseTilt) + ( holderBottomDepth + holderLidGap ) * sin(caseTilt) ) - 11 mm )"
equation "d2730 = bottomThickness"
equation "d2732 = ( ( 115 mm ) - holderStemX ) + ( -2.5 mm ) - 1.2 mm"
equation "d2733 = ( ( ( ( keyRowOne ) - holderStemY ) - 1.2 mm ) * cos(caseTilt) + ( holderBottomDepth + holderLidGap ) * sin(caseTilt) ) - 2.5 mm"
equation "d2734 = ( ( ( ( 115 mm ) - holderStemX ) + ( -2.5 mm ) - 1.2 mm ) + ( 2.4 mm ) ) - ( ( ( 115 mm ) - holderStemX ) + ( -2.5 mm ) - 1.2 mm )"
equation "d2735 = ( ( ( ( ( ( keyRowOne ) - holderStemY ) - 1.2 mm ) * cos(caseTilt) + ( holderBottomDepth + holderLidGap ) * sin(caseTilt) ) - 2.5 mm ) + ( 5 mm ) ) - ( ( ( ( ( keyRowOne ) - holderStemY ) - 1.2 mm ) * cos(caseTilt) + ( holderBottomDepth + holderLidGap ) * sin(caseTilt) ) - 2.5 mm )"
equation "d2736 = ( frontHeight + ( ( ( keyRowOne ) - holderStemY ) - 1.2 mm ) * sin(caseTilt) - ( holderBottomDepth + holderLidGap ) * cos(caseTilt) ) - bottomThickness - 2 mm"
equation "d2738 = ( ( 115 mm ) - holderStemX ) + ( -2.5 mm ) - 0.5 mm"
equation "d2739 = ( ( ( ( keyRowOne ) - holderStemY ) - 1.2 mm ) * cos(caseTilt) + ( holderBottomDepth + holderLidGap ) * sin(caseTilt) ) - 1.5 mm"
equation "d2740 = ( ( ( ( 115 mm ) - holderStemX ) + ( -2.5 mm ) - 0.5 mm ) + ( 1 mm ) ) - ( ( ( 115 mm ) - holderStemX ) + ( -2.5 mm ) - 0.5 mm )"
equation "d2741 = ( ( ( ( ( ( keyRowOne ) - holderStemY ) - 1.2 mm ) * cos(caseTilt) + ( holderBottomDepth + holderLidGap ) * sin(caseTilt) ) - 1.5 mm ) + ( 3 mm ) ) - ( ( ( ( ( keyRowOne ) - holderStemY ) - 1.2 mm ) * cos(caseTilt) + ( holderBottomDepth + holderLidGap ) * sin(caseTilt) ) - 1.5 mm )"
equation "d2742 = ( frontHeight + ( ( ( keyRowOne ) - holderStemY ) - 1.2 mm ) * sin(caseTilt) - ( holderBottomDepth + holderLidGap ) * cos(caseTilt) ) - bottomThickness + 0.5 mm"
equation "d2744 = ( ( ( 115 mm ) - holderStemX ) + ( -2.5 mm ) - 0.5 mm ) - 0.1 mm"
equation "d2745 = ( ( ( ( keyRowOne ) - holderStemY ) - 1.2 mm ) - 2 mm ) + faceOriginV"
equation "d2746 = ( ( ( ( ( 115 mm ) - holderStemX ) + ( -2.5 mm ) - 0.5 mm ) - 0.1 mm ) + ( 1.2 mm ) ) - ( ( ( ( 115 mm ) - holderStemX ) + ( -2.5 mm ) - 0.5 mm ) - 0.1 mm )"
equation "d2747 = ( ( ( ( ( ( keyRowOne ) - holderStemY ) - 1.2 mm ) - 2 mm ) + faceOriginV ) + ( 4 mm ) ) - ( ( ( ( ( keyRowOne ) - holderStemY ) - 1.2 mm ) - 2 mm ) + faceOriginV )"
equation "d2748 = rearHeight"
equation "d2750 = ( ( 115 mm ) - holderStemX ) + ( 2.5 mm ) - 1.2 mm"
equation "d2751 = ( ( ( ( keyRowOne ) - holderStemY ) - 1.2 mm ) * cos(caseTilt) + ( holderBottomDepth + holderLidGap ) * sin(caseTilt) ) - 2.5 mm"
equation "d2752 = ( ( ( ( 115 mm ) - holderStemX ) + ( 2.5 mm ) - 1.2 mm ) + ( 2.4 mm ) ) - ( ( ( 115 mm ) - holderStemX ) + ( 2.5 mm ) - 1.2 mm )"
equation "d2753 = ( ( ( ( ( ( keyRowOne ) - holderStemY ) - 1.2 mm ) * cos(caseTilt) + ( holderBottomDepth + holderLidGap ) * sin(caseTilt) ) - 2.5 mm ) + ( 5 mm ) ) - ( ( ( ( ( keyRowOne ) - holderStemY ) - 1.2 mm ) * cos(caseTilt) + ( holderBottomDepth + holderLidGap ) * sin(caseTilt) ) - 2.5 mm )"
equation "d2754 = ( frontHeight + ( ( ( keyRowOne ) - holderStemY ) - 1.2 mm ) * sin(caseTilt) - ( holderBottomDepth + holderLidGap ) * cos(caseTilt) ) - bottomThickness - 2 mm"
equation "d2756 = ( ( 115 mm ) - holderStemX ) + ( 2.5 mm ) - 0.5 mm"
equation "d2757 = ( ( ( ( keyRowOne ) - holderStemY ) - 1.2 mm ) * cos(caseTilt) + ( holderBottomDepth + holderLidGap ) * sin(caseTilt) ) - 1.5 mm"
equation "d2758 = ( ( ( ( 115 mm ) - holderStemX ) + ( 2.5 mm ) - 0.5 mm ) + ( 1 mm ) ) - ( ( ( 115 mm ) - holderStemX ) + ( 2.5 mm ) - 0.5 mm )"
equation "d2759 = ( ( ( ( ( ( keyRowOne ) - holderStemY ) - 1.2 mm ) * cos(caseTilt) + ( holderBottomDepth + holderLidGap ) * sin(caseTilt) ) - 1.5 mm ) + ( 3 mm ) ) - ( ( ( ( ( keyRowOne ) - holderStemY ) - 1.2 mm ) * cos(caseTilt) + ( holderBottomDepth + holderLidGap ) * sin(caseTilt) ) - 1.5 mm )"
equation "d2760 = ( frontHeight + ( ( ( keyRowOne ) - holderStemY ) - 1.2 mm ) * sin(caseTilt) - ( holderBottomDepth + holderLidGap ) * cos(caseTilt) ) - bottomThickness + 0.5 mm"
equation "d2762 = ( ( ( 115 mm ) - holderStemX ) + ( 2.5 mm ) - 0.5 mm ) - 0.1 mm"
equation "d2763 = ( ( ( ( keyRowOne ) - holderStemY ) - 1.2 mm ) - 2 mm ) + faceOriginV"
equation "d2764 = ( ( ( ( ( 115 mm ) - holderStemX ) + ( 2.5 mm ) - 0.5 mm ) - 0.1 mm ) + ( 1.2 mm ) ) - ( ( ( ( 115 mm ) - holderStemX ) + ( 2.5 mm ) - 0.5 mm ) - 0.1 mm )"
equation "d2765 = ( ( ( ( ( ( keyRowOne ) - holderStemY ) - 1.2 mm ) - 2 mm ) + faceOriginV ) + ( 4 mm ) ) - ( ( ( ( ( keyRowOne ) - holderStemY ) - 1.2 mm ) - 2 mm ) + faceOriginV )"
equation "d2766 = rearHeight"
named bodies: "UpperShell_Draft", "MiddleCarrier_Draft", "BottomCover_Draft", "Diffuser_Draft", "SwitchFitCoupon_Trial", "LidSupportCoupon_Trial"
